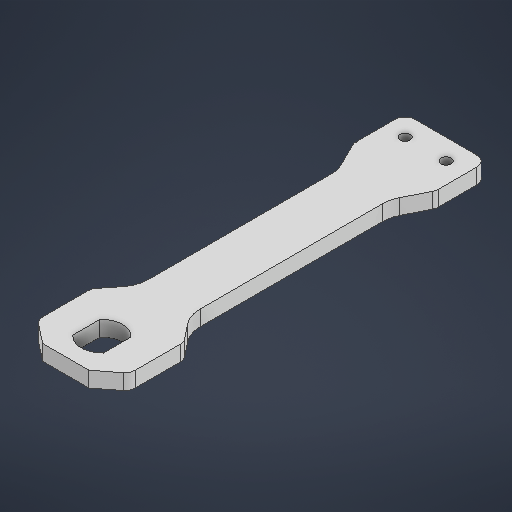
# Autodesk Inventor part: thanh lk 2
Saved by Autodesk Inventor 2027 (Build 310192060, 192F)
## iProperties
Created: 2026-08-19
Part Number: thanh lk 2
Material: Generic
Document SubType Name: Modeling
Designer: thita
Density: 1 g/cm^3
Appearance: Default
Author: thita
Autodesk Inventor part; units mm, degrees
ref_plane "YZ Plane" through (0, 0, 0) normal (1, 0, 0) x (0, 1, 0)
ref_plane "XZ Plane" through (0, 0, 0) normal (0, 1, 0) x (-1, 0, 0)
ref_plane "XY Plane" through (0, 0, 0) normal (0, 0, 1) x (1, 0, 0)
sketch "Sketch1" plane through (0, 0, 0) normal (0, 1, 0) x (-1, 0, 0)
  line L0 (3, -2.6458) -> (3, 2.6458)
  arc A0 (3, 2.6458) -> (-3, 2.6458) centre (0, 0) ccw
  arc A1 (-3, -2.6458) -> (3, -2.6458) centre (0, 0) ccw
  line L1 (-3, 2.6458) -> (-3, -2.6458)
  line L2 (-9, -6.2984) -> (-9, 2.5218)
  line L3 (-9, 7) -> (9, -7) construction
  line L4 (9, 7) -> (-9, -7) construction
  circle A2 centre (4, -63) radius 1
  circle A3 centre (-4, -63) radius 1
  line L5 (-6, -67) -> (6, -67)
  line L6 (8, -67) -> (-8, -67)
  line L7 (-8, -65) -> (-8, -57.4721)
  line L8 (8, -57.4721) -> (8, -65)
  arc A4 (6, -67) -> (8, -65) centre (6, -65) ccw
  arc A5 (-8, -65) -> (-6, -67) centre (-6, -65) ccw
  line L9 (7.7889, -56.5777) -> (5.6334, -52.2669)
  line L10 (-7.7889, -56.5777) -> (-5.6334, -52.2669)
  arc A6 (5, -49.5836) -> (5.6334, -52.2669) centre (11, -49.5836) ccw
  arc A7 (-5.6334, -52.2669) -> (-5, -49.5836) centre (-11, -49.5836) ccw
  arc A8 (8, -57.4721) -> (7.7889, -56.5777) centre (6, -57.4721) ccw
  arc A9 (-7.7889, -56.5777) -> (-8, -57.4721) centre (-6, -57.4721) ccw
  line L11 (8.5617, -7.5478) -> (6.3148, -10.3565)
  line L12 (-8.5617, -7.5478) -> (-6.3148, -10.3565)
  arc A10 (6.3148, -10.3565) -> (5, -14.1047) centre (11, -14.1047) ccw
  arc A11 (-5, -14.1047) -> (-6.3148, -10.3565) centre (-11, -14.1047) ccw
  arc A12 (8.5617, -7.5478) -> (9, -6.2984) centre (7, -6.2984) ccw
  arc A13 (-9, -6.2984) -> (-8.5617, -7.5478) centre (-7, -6.2984) ccw
  line L13 (-8.2279, 4.1005) -> (-4.5, 7)
  arc A14 (-8.2279, 4.1005) -> (-9, 2.5218) centre (-7, 2.5218) ccw
  line L14 (0, 7) -> (-4.5, 7)
  line L15 (8.2279, 4.1005) -> (4.5, 7)
  arc A15 (9, 2.5218) -> (8.2279, 4.1005) centre (7, 2.5218) ccw
  line L16 (0, 7) -> (4.5, 7)
  line L17 (9, 2.5218) -> (9, -6.2984)
  line L18 (0, -67) -> (0, -63)
  line L19 (4, -63) -> (-4, -63)
  line L20 (0, -63) -> (0, -61.6991)
  line L21 (5, -14.1047) -> (5, -49.5836)
  line L22 (-5, -49.5836) -> (-5, -14.1047)
  point P0 (0, 0)
  point P1 (-8, -57)
  point P2 (-5, -51)
  point P3 (-9, 3.5)
  point P4 (9, 3.5)
  point P5 (-5, -14.1047)
  dimension "d0" = 18
  dimension "d1" = 14
  dimension "d2" = 63
  dimension "d4" = 2
  dimension "d5" = 2
  dimension "d10" = 10
  dimension "d11" = 2
  dimension "d12" = 2
  dimension "d14" = 6
  dimension "d15" = 2
  dimension "d18" = 6
  dimension "d19" = 2
  dimension "d20" = 2
  constraints: 46 end point, 28 point on circle, 17 tangent, 16 centre point, 12 point on line, 4 equal radius, 4 midpoint, 4 vertical, 2 horizontal, 1 parallel, 1 perpendicular
  measures "d0" distance of L3.start L4.start
  measures "d1" distance of L4.start L3.end
  measures "d2" distance of A1.centre L18.end
  measures "d4" diameter of A2
  measures "d5" diameter of A3
  measures "d10" distance of L6.end point (-8, -57)
  measures "d11" radius of A4
  measures "d12" radius of A5
  measures "d14" radius of A6
  measures "d15" radius of A8
  measures "d18" radius of A10
  measures "d19" radius of A12
  measures "d20" radius of A14
extrude "Extrusion1" add sketch "Sketch1" along normal blind 3
body "Solid1"
